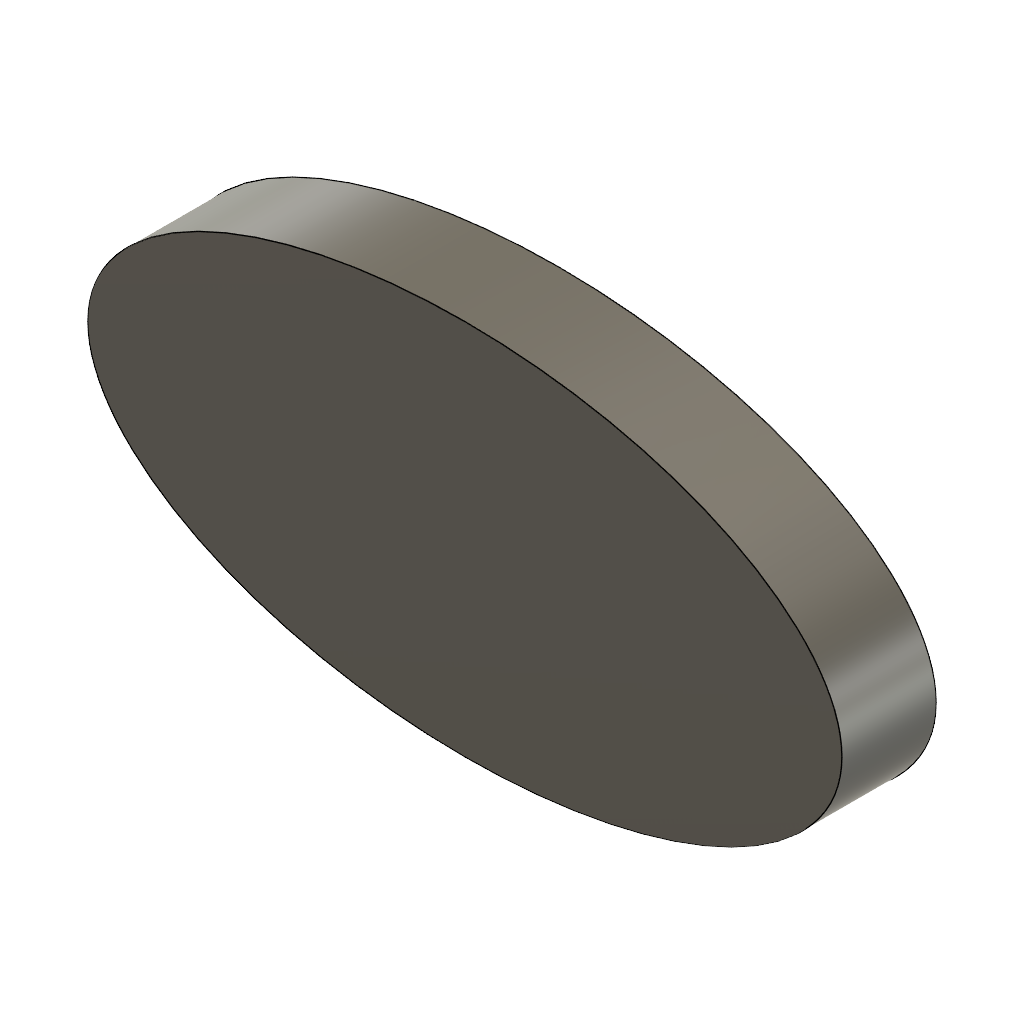
sk_ellipse (Autodesk Fusion 360 design; units mm, degrees)
part number: 2026-11-13-14-35-20-722
Autodesk Fusion 360 part; units mm, degrees
sketch "Sketch1" plane through (0, 0, 0) normal (0, 0, 1) x (1, 0, 0)
  ellipse E0 centre (0, 0) end of major axis (20, 0) minor radius 10
  line L0 (-20, 0) -> (20, 0) construction
  line L1 (0, 10) -> (0, -10) construction
  constraint coincident E0 L0.start
  constraint coincident E0 L0.end
  constraint coincident E0 L1.start
  constraint coincident E0 L1.end
extrude "Extrude1" add sketch "Sketch1" along normal blind 5
